Autodesk Fusion 360 part; units mm, degrees
(part 4 of 5)
  spline S15 degree 5 poles (5.856777, 3.833819) (5.854947, 3.833842) (5.851291, 3.833884) (5.845814, 3.833942) (5.838525, 3.834007) (5.829438, 3.834066) (5.820373, 3.834104) (5.811333, 3.834121) (5.802315, 3.834116) (5.793322, 3.83409) (5.784352, 3.834043) (5.775406, 3.833975) (5.766483, 3.833886) (5.757585, 3.833776) (5.748711, 3.833645) (5.739862, 3.833494) (5.731037, 3.833323) (5.722236, 3.833131) (5.71346, 3.832918) (5.704709, 3.832686) (5.695983, 3.832433) (5.687281, 3.83216) (5.678605, 3.831868) (5.669954, 3.831555) (5.661328, 3.831223) (5.652728, 3.830871) (5.644153, 3.8305) (5.635603, 3.830109) (5.62708, 3.829699) (5.618582, 3.82927) (5.610111, 3.828821) (5.601665, 3.828354) (5.593246, 3.827868) (5.584853, 3.827362) (5.576486, 3.826839) (5.568146, 3.826296) (5.559832, 3.825735) (5.551545, 3.825156) (5.543285, 3.824559) (5.535052, 3.823943) (5.526846, 3.82331) (5.518668, 3.822658) (5.510516, 3.821989) (5.502392, 3.821302) (5.494296, 3.820597) (5.486227, 3.819875) (5.478186, 3.819136) (5.470173, 3.818379) (5.462188, 3.817606) (5.454231, 3.816815) (5.446302, 3.816008) (5.438401, 3.815183) (5.430529, 3.814343) (5.422685, 3.813485) (5.41487, 3.812611) (5.407084, 3.811721) (5.399327, 3.810815) (5.391598, 3.809893) (5.383899, 3.808955) (5.376229, 3.808002) (5.368589, 3.807032) (5.360978, 3.806047) (5.353396, 3.805047) (5.345844, 3.804032) (5.338322, 3.803001) (5.33083, 3.801956) (5.323367, 3.800896) (5.315935, 3.799821) (5.308534, 3.798731) (5.301162, 3.797627) (5.293821, 3.796509) (5.286511, 3.795376) (5.279231, 3.79423) (5.271982, 3.79307) (5.264764, 3.791896) (5.257578, 3.790708) (5.250422, 3.789507) (5.243298, 3.788293) (5.236205, 3.787065) (5.229143, 3.785825) (5.222113, 3.784571) (5.215115, 3.783305) (5.208149, 3.782027) (5.201215, 3.780736) (5.194313, 3.779432) (5.187443, 3.778117) (5.180605, 3.77679) (5.1738, 3.77545) (5.167028, 3.7741) (5.160288, 3.772737) (5.153581, 3.771364) (5.146907, 3.769979) (5.140266, 3.768583) (5.133658, 3.767176) (5.127083, 3.765759) (5.120542, 3.764331) (5.114034, 3.762893) (5.10756, 3.761444) (5.10112, 3.759986) (5.094713, 3.758518) (5.08834, 3.75704) (5.082002, 3.755552) (5.075698, 3.754055) (5.069428, 3.752549) (5.063192, 3.751034) (5.056991, 3.74951) (5.050825, 3.747978) (5.044694, 3.746437) (5.038597, 3.744887) (5.032536, 3.74333) (5.026509, 3.741764) (5.020518, 3.740191) (5.014563, 3.738611) (5.008643, 3.737023) (5.002758, 3.735427) (4.99691, 3.733825) (4.991097, 3.732216) (4.98532, 3.730601) (4.97958, 3.728979) (4.973875, 3.72735) (4.968207, 3.725716) (4.962576, 3.724076) (4.956981, 3.72243) (4.951422, 3.720779) (4.945901, 3.719122) (4.940417, 3.717461) (4.934969, 3.715795) (4.929559, 3.714124) (4.924187, 3.712448) (4.918851, 3.710769) (4.913554, 3.709085) (4.908294, 3.707398) (4.903072, 3.705707) (4.897887, 3.704013) (4.892741, 3.702316) (4.887633, 3.700616) (4.882564, 3.698913) (4.877533, 3.697207) (4.87254, 3.6955) (4.867586, 3.69379) (4.862671, 3.692079) (4.857795, 3.690366) (4.852958, 3.688652) (4.84816, 3.686937) (4.843402, 3.685221) (4.838682, 3.683504) (4.834003, 3.681787) (4.829363, 3.68007) (4.824763, 3.678353) (4.820203, 3.676636) (4.815683, 3.67492) (4.811203, 3.673205) (4.806764, 3.671491) (4.802365, 3.669779) (4.798006, 3.668068) (4.793688, 3.666359) (4.789412, 3.664652) (4.785176, 3.662947) (4.780981, 3.661246) (4.776827, 3.659547) (4.772715, 3.657851) (4.768644, 3.656159) (4.764615, 3.654471) (4.760627, 3.652787) (4.756682, 3.651107) (4.752778, 3.649432) (4.748917, 3.647762) (4.745097, 3.646097) (4.741321, 3.644437) (4.737586, 3.642784) (4.733895, 3.641136) (4.730246, 3.639495) (4.72664, 3.63786) (4.723077, 3.636233) (4.719557, 3.634612) (4.716081, 3.633) (4.712648, 3.631395) (4.709258, 3.629799) (4.705913, 3.628211) (4.702611, 3.626632) (4.699353, 3.625062) (4.696139, 3.623502) (4.69297, 3.621952) (4.689845, 3.620411) (4.686764, 3.618882) (4.683728, 3.617363) (4.680737, 3.615856) (4.677791, 3.61436) (4.67489, 3.612876) (4.672034, 3.611405) (4.669224, 3.609946) (4.666459, 3.6085) (4.663739, 3.607067) (4.661066, 3.605649) (4.658438, 3.604244) (4.655856, 3.602854) (4.653321, 3.601479) (4.650832, 3.600119) (4.648389, 3.598775) (4.645993, 3.597447) (4.643644, 3.596136) (4.641342, 3.594841) (4.639087, 3.593564) (4.636879, 3.592304) (4.634718, 3.591063) (4.632605, 3.58984) (4.63054, 3.588636) (4.628522, 3.587452) (4.626553, 3.586287) (4.624631, 3.585143) (4.622758, 3.58402) (4.620933, 3.582917) (4.619157, 3.581837) (4.617429, 3.580778) (4.61575, 3.579743) (4.614121, 3.57873) (4.61254, 3.577741) (4.611009, 3.576776) (4.609527, 3.575835) (4.608095, 3.57492) (4.606713, 3.57403) (4.605381, 3.573166) (4.604099, 3.572329) (4.602867, 3.571519) (4.601685, 3.570737) (4.600555, 3.569983) (4.599475, 3.569257) (4.598446, 3.568561) (4.597468, 3.567895) (4.596541, 3.56726) (4.595666, 3.566655) (4.594843, 3.566083) (4.594071, 3.565542) (4.593351, 3.565034) (4.592683, 3.56456) (4.592068, 3.564119) (4.591505, 3.563713) (4.590995, 3.563343) (4.590538, 3.563009) (4.590134, 3.562712) (4.589784, 3.562453) (4.589546, 3.562275) (4.589391, 3.562159) (4.589299, 3.562089) (4.589256, 3.562056) knots -1 -1 -1 -1 -1 -1 -0.99583333 -0.99166667 -0.9875 -0.98333333 -0.97916667 -0.975 -0.97083333 -0.96666667 -0.9625 -0.95833333 -0.95416667 -0.95 -0.94583333 -0.94166667 -0.9375 -0.93333333 -0.92916667 -0.925 -0.92083333 -0.91666667 -0.9125 -0.90833333 -0.90416667 -0.9 -0.89583333 -0.89166667 -0.8875 -0.88333333 -0.87916667 -0.875 -0.87083333 -0.86666667 -0.8625 -0.85833333 -0.85416667 -0.85 -0.84583333 -0.84166667 -0.8375 -0.83333333 -0.82916667 -0.825 -0.82083333 -0.81666667 -0.8125 -0.80833333 -0.80416667 -0.8 -0.79583333 -0.79166667 -0.7875 -0.78333333 -0.77916667 -0.775 -0.77083333 -0.76666667 -0.7625 -0.75833333 -0.75416667 -0.75 -0.74583333 -0.74166667 -0.7375 -0.73333333 -0.72916667 -0.725 -0.72083333 -0.71666667 -0.7125 -0.70833333 -0.70416667 -0.7 -0.69583333 -0.69166667 -0.6875 -0.68333333 -0.67916667 -0.675 -0.67083333 -0.66666667 -0.6625 -0.65833333 -0.65416667 -0.65 -0.64583333 -0.64166667 -0.6375 -0.63333333 -0.62916667 -0.625 -0.62083333 -0.61666667 -0.6125 -0.60833333 -0.60416667 -0.6 -0.59583333 -0.59166667 -0.5875 -0.58333333 -0.57916667 -0.575 -0.57083333 -0.56666667 -0.5625 -0.55833333 -0.55416667 -0.55 -0.54583333 -0.54166667 -0.5375 -0.53333333 -0.52916667 -0.525 -0.52083333 -0.51666667 -0.5125 -0.50833333 -0.50416667 -0.5 -0.49583333 -0.49166667 -0.4875 -0.48333333 -0.47916667 -0.475 -0.47083333 -0.46666667 -0.4625 -0.45833333 -0.45416667 -0.45 -0.44583333 -0.44166667 -0.4375 -0.43333333 -0.42916667 -0.425 -0.42083333 -0.41666667 -0.4125 -0.40833333 -0.40416667 -0.4 -0.39583333 -0.39166667 -0.3875 -0.38333333 -0.37916667 -0.375 -0.37083333 -0.36666667 -0.3625 -0.35833333 -0.35416667 -0.35 -0.34583333 -0.34166667 -0.3375 -0.33333333 -0.32916667 -0.325 -0.32083333 -0.31666667 -0.3125 -0.30833333 -0.30416667 -0.3 -0.29583333 -0.29166667 -0.2875 -0.28333333 -0.27916667 -0.275 -0.27083333 -0.26666667 -0.2625 -0.25833333 -0.25416667 -0.25 -0.24583333 -0.24166667 -0.2375 -0.23333333 -0.22916667 -0.225 -0.22083333 -0.21666667 -0.2125 -0.20833333 -0.20416667 -0.2 -0.19583333 -0.19166667 -0.1875 -0.18333333 -0.17916667 -0.175 -0.17083333 -0.16666667 -0.1625 -0.15833333 -0.15416667 -0.15 -0.14583333 -0.14166667 -0.1375 -0.13333333 -0.12916667 -0.125 -0.12083333 -0.11666667 -0.1125 -0.10833333 -0.10416667 -0.1 -0.09583333 -0.09166667 -0.0875 -0.08333333 -0.07916667 -0.075 -0.07083333 -0.06666667 -0.0625 -0.05833333 -0.05416667 -0.05 -0.04583333 -0.04166667 -0.0375 -0.03333333 -0.02916667 -0.025 -0.02083333 -0.01666667 -0.0125 -0.00833333 -0.00416667 0 0 0 0 0 0
  line L30 (4.589256, 3.562056) -> (4.58882, 3.561725)
  line L31 (4.58882, 3.561725) -> (3.752337, 2.912468)
  arc A16 (3.752337, 2.912468) -> (2.912468, 3.752337) centre (0, 0) ccw
  line L32 (2.912468, 3.752337) -> (3.561725, 4.58882)
  line L33 (3.561725, 4.58882) -> (3.562056, 4.589256)
  spline S16 degree 5 poles (3.562056, 4.589256) (3.562089, 4.589299) (3.562159, 4.589391) (3.562275, 4.589546) (3.562453, 4.589784) (3.562712, 4.590134) (3.563009, 4.590538) (3.563343, 4.590995) (3.563713, 4.591505) (3.564119, 4.592068) (3.56456, 4.592683) (3.565034, 4.593351) (3.565542, 4.594071) (3.566083, 4.594843) (3.566655, 4.595666) (3.56726, 4.596541) (3.567895, 4.597468) (3.568561, 4.598446) (3.569257, 4.599475) (3.569983, 4.600555) (3.570737, 4.601685) (3.571519, 4.602867) (3.572329, 4.604099) (3.573166, 4.605381) (3.57403, 4.606713) (3.57492, 4.608095) (3.575835, 4.609527) (3.576776, 4.611009) (3.577741, 4.61254) (3.57873, 4.614121) (3.579743, 4.61575) (3.580778, 4.617429) (3.581837, 4.619157) (3.582917, 4.620933) (3.58402, 4.622758) (3.585143, 4.624631) (3.586287, 4.626553) (3.587452, 4.628522) (3.588636, 4.63054) (3.58984, 4.632605) (3.591063, 4.634718) (3.592304, 4.636879) (3.593564, 4.639087) (3.594841, 4.641342) (3.596136, 4.643644) (3.597447, 4.645993) (3.598775, 4.648389) (3.600119, 4.650832) (3.601479, 4.653321) (3.602854, 4.655856) (3.604244, 4.658438) (3.605649, 4.661066) (3.607067, 4.663739) (3.6085, 4.666459) (3.609946, 4.669224) (3.611405, 4.672034) (3.612876, 4.67489) (3.61436, 4.677791) (3.615856, 4.680737) (3.617363, 4.683728) (3.618882, 4.686764) (3.620411, 4.689845) (3.621952, 4.69297) (3.623502, 4.696139) (3.625062, 4.699353) (3.626632, 4.702611) (3.628211, 4.705913) (3.629799, 4.709258) (3.631395, 4.712648) (3.633, 4.716081) (3.634612, 4.719557) (3.636233, 4.723077) (3.63786, 4.72664) (3.639495, 4.730246) (3.641136, 4.733895) (3.642784, 4.737586) (3.644437, 4.741321) (3.646097, 4.745097) (3.647762, 4.748917) (3.649432, 4.752778) (3.651107, 4.756682) (3.652787, 4.760627) (3.654471, 4.764615) (3.656159, 4.768644) (3.657851, 4.772715) (3.659547, 4.776827) (3.661246, 4.780981) (3.662947, 4.785176) (3.664652, 4.789412) (3.666359, 4.793688) (3.668068, 4.798006) (3.669779, 4.802365) (3.671491, 4.806764) (3.673205, 4.811203) (3.67492, 4.815683) (3.676636, 4.820203) (3.678353, 4.824763) (3.68007, 4.829363) (3.681787, 4.834003) (3.683504, 4.838682) (3.685221, 4.843402) (3.686937, 4.84816) (3.688652, 4.852958) (3.690366, 4.857795) (3.692079, 4.862671) (3.69379, 4.867586) (3.6955, 4.87254) (3.697207, 4.877533) (3.698913, 4.882564) (3.700616, 4.887633) (3.702316, 4.892741) (3.704013, 4.897887) (3.705707, 4.903072) (3.707398, 4.908294) (3.709085, 4.913554) (3.710769, 4.918851) (3.712448, 4.924187) (3.714124, 4.929559) (3.715795, 4.934969) (3.717461, 4.940417) (3.719122, 4.945901) (3.720779, 4.951422) (3.72243, 4.956981) (3.724076, 4.962576) (3.725716, 4.968207) (3.72735, 4.973875) (3.728979, 4.97958) (3.730601, 4.98532) (3.732216, 4.991097) (3.733825, 4.99691) (3.735427, 5.002758) (3.737023, 5.008643) (3.738611, 5.014563) (3.740191, 5.020518) (3.741764, 5.026509) (3.74333, 5.032536) (3.744887, 5.038597) (3.746437, 5.044694) (3.747978, 5.050825) (3.74951, 5.056991) (3.751034, 5.063192) (3.752549, 5.069428) (3.754055, 5.075698) (3.755552, 5.082002) (3.75704, 5.08834) (3.758518, 5.094713) (3.759986, 5.10112) (3.761444, 5.10756) (3.762893, 5.114034) (3.764331, 5.120542) (3.765759, 5.127083) (3.767176, 5.133658) (3.768583, 5.140266) (3.769979, 5.146907) (3.771364, 5.153581) (3.772737, 5.160288) (3.7741, 5.167028) (3.77545, 5.1738) (3.77679, 5.180605) (3.778117, 5.187443) (3.779432, 5.194313) (3.780736, 5.201215) (3.782027, 5.208149) (3.783305, 5.215115) (3.784571, 5.222113) (3.785825, 5.229143) (3.787065, 5.236205) (3.788293, 5.243298) (3.789507, 5.250422) (3.790708, 5.257578) (3.791896, 5.264764) (3.79307, 5.271982) (3.79423, 5.279231) (3.795376, 5.286511) (3.796509, 5.293821) (3.797627, 5.301162) (3.798731, 5.308534) (3.799821, 5.315935) (3.800896, 5.323367) (3.801956, 5.33083) (3.803001, 5.338322) (3.804032, 5.345844) (3.805047, 5.353396) (3.806047, 5.360978) (3.807032, 5.368589) (3.808002, 5.376229) (3.808955, 5.383899) (3.809893, 5.391598) (3.810815, 5.399327) (3.811721, 5.407084) (3.812611, 5.41487) (3.813485, 5.422685) (3.814343, 5.430529) (3.815183, 5.438401) (3.816008, 5.446302) (3.816815, 5.454231) (3.817606, 5.462188) (3.818379, 5.470173) (3.819136, 5.478186) (3.819875, 5.486227) (3.820597, 5.494296) (3.821302, 5.502392) (3.821989, 5.510516) (3.822658, 5.518668) (3.82331, 5.526846) (3.823943, 5.535052) (3.824559, 5.543285) (3.825156, 5.551545) (3.825735, 5.559832) (3.826296, 5.568146) (3.826839, 5.576486) (3.827362, 5.584853) (3.827868, 5.593246) (3.828354, 5.601665) (3.828821, 5.610111) (3.82927, 5.618582) (3.829699, 5.62708) (3.830109, 5.635603) (3.8305, 5.644153) (3.830871, 5.652728) (3.831223, 5.661328) (3.831555, 5.669954) (3.831868, 5.678605) (3.83216, 5.687281) (3.832433, 5.695983) (3.832686, 5.704709) (3.832918, 5.71346) (3.833131, 5.722236) (3.833323, 5.731037) (3.833494, 5.739862) (3.833645, 5.748711) (3.833776, 5.757585) (3.833886, 5.766483) (3.833975, 5.775406) (3.834043, 5.784352) (3.83409, 5.793322) (3.834116, 5.802315) (3.834121, 5.811333) (3.834104, 5.820373) (3.834066, 5.829438) (3.834007, 5.838525) (3.833942, 5.845814) (3.833884, 5.851291) (3.833842, 5.854947) (3.833819, 5.856777) knots 0 0 0 0 0 0 0.00416667 0.00833333 0.0125 0.01666667 0.02083333 0.025 0.02916667 0.03333333 0.0375 0.04166667 0.04583333 0.05 0.05416667 0.05833333 0.0625 0.06666667 0.07083333 0.075 0.07916667 0.08333333 0.0875 0.09166667 0.09583333 0.1 0.10416667 0.10833333 0.1125 0.11666667 0.12083333 0.125 0.12916667 0.13333333 0.1375 0.14166667 0.14583333 0.15 0.15416667 0.15833333 0.1625 0.16666667 0.17083333 0.175 0.17916667 0.18333333 0.1875 0.19166667 0.19583333 0.2 0.20416667 0.20833333 0.2125 0.21666667 0.22083333 0.225 0.22916667 0.23333333 0.2375 0.24166667 0.24583333 0.25 0.25416667 0.25833333 0.2625 0.26666667 0.27083333 0.275 0.27916667 0.28333333 0.2875 0.29166667 0.29583333 0.3 0.30416667 0.30833333 0.3125 0.31666667 0.32083333 0.325 0.32916667 0.33333333 0.3375 0.34166667 0.34583333 0.35 0.35416667 0.35833333 0.3625 0.36666667 0.37083333 0.375 0.37916667 0.38333333 0.3875 0.39166667 0.39583333 0.4 0.40416667 0.40833333 0.4125 0.41666667 0.42083333 0.425 0.42916667 0.43333333 0.4375 0.44166667 0.44583333 0.45 0.45416667 0.45833333 0.4625 0.46666667 0.47083333 0.475 0.47916667 0.48333333 0.4875 0.49166667 0.49583333 0.5 0.50416667 0.50833333 0.5125 0.51666667 0.52083333 0.525 0.52916667 0.53333333 0.5375 0.54166667 0.54583333 0.55 0.55416667 0.55833333 0.5625 0.56666667 0.57083333 0.575 0.57916667 0.58333333 0.5875 0.59166667 0.59583333 0.6 0.60416667 0.60833333 0.6125 0.61666667 0.62083333 0.625 0.62916667 0.63333333 0.6375 0.64166667 0.64583333 0.65 0.65416667 0.65833333 0.6625 0.66666667 0.67083333 0.675 0.67916667 0.68333333 0.6875 0.69166667 0.69583333 0.7 0.70416667 0.70833333 0.7125 0.71666667 0.72083333 0.725 0.72916667 0.73333333 0.7375 0.74166667 0.74583333 0.75 0.75416667 0.75833333 0.7625 0.76666667 0.77083333 0.775 0.77916667 0.78333333 0.7875 0.79166667 0.79583333 0.8 0.80416667 0.80833333 0.8125 0.81666667 0.82083333 0.825 0.82916667 0.83333333 0.8375 0.84166667 0.84583333 0.85 0.85416667 0.85833333 0.8625 0.86666667 0.87083333 0.875 0.87916667 0.88333333 0.8875 0.89166667 0.89583333 0.9 0.90416667 0.90833333 0.9125 0.91666667 0.92083333 0.925 0.92916667 0.93333333 0.9375 0.94166667 0.94583333 0.95 0.95416667 0.95833333 0.9625 0.96666667 0.97083333 0.975 0.97916667 0.98333333 0.9875 0.99166667 0.99583333 1 1 1 1 1 1
  arc A17 (3.833819, 5.856777) -> (3.155208, 6.248573) centre (0, 0) ccw
  spline S17 degree 5 poles (3.155208, 6.248573) (3.153612, 6.247678) (3.150425, 6.245887) (3.145652, 6.243199) (3.139308, 6.23961) (3.131408, 6.235117) (3.123539, 6.230618) (3.115701, 6.226112) (3.107895, 6.2216) (3.100119, 6.21708) (3.092374, 6.212555) (3.084661, 6.208022) (3.076978, 6.203484) (3.069327, 6.19894) (3.061707, 6.19439) (3.054119, 6.189834) (3.046562, 6.185273) (3.039036, 6.180707) (3.031542, 6.176135) (3.02408, 6.171558) (3.016649, 6.166976) (3.00925, 6.162389) (3.001882, 6.157797) (2.994546, 6.153201) (2.987242, 6.148601) (2.97997, 6.143996) (2.97273, 6.139387) (2.965521, 6.134774) (2.958345, 6.130157) (2.9512, 6.125536) (2.944088, 6.120912) (2.937007, 6.116284) (2.929959, 6.111653) (2.922943, 6.107019) (2.915959, 6.102382) (2.909007, 6.097743) (2.902088, 6.0931) (2.895201, 6.088455) (2.888347, 6.083808) (2.881524, 6.079158) (2.874735, 6.074507) (2.867977, 6.069853) (2.861253, 6.065198) (2.854561, 6.060541) (2.847901, 6.055882) (2.841274, 6.051223) (2.83468, 6.046562) (2.828119, 6.0419) (2.82159, 6.037237) (2.815095, 6.032574) (2.808632, 6.02791) (2.802202, 6.023246) (2.795805, 6.018582) (2.789441, 6.013918) (2.78311, 6.009253) (2.776811, 6.00459) (2.770546, 5.999926) (2.764315, 5.995264) (2.758116, 5.990602) (2.75195, 5.985941) (2.745818, 5.981281) (2.739719, 5.976622) (2.733653, 5.971966) (2.727621, 5.96731) (2.721622, 5.962657) (2.715656, 5.958005) (2.709724, 5.953356) (2.703825, 5.948709) (2.697959, 5.944064) (2.692128, 5.939423) (2.686329, 5.934784) (2.680564, 5.930148) (2.674833, 5.925515) (2.669136, 5.920886) (2.663472, 5.91626) (2.657842, 5.911638) (2.652245, 5.90702) (2.646683, 5.902407) (2.641154, 5.897797) (2.635658, 5.893192) (2.630197, 5.888592) (2.62477, 5.883996) (2.619376, 5.879406) (2.614016, 5.874821) (2.608691, 5.870241) (2.603399, 5.865667) (2.598141, 5.861098) (2.592917, 5.856536) (2.587728, 5.85198) (2.582572, 5.84743) (2.57745, 5.842887) (2.572363, 5.838351) (2.567309, 5.833822) (2.56229, 5.829299) (2.557305, 5.824785) (2.552354, 5.820277) (2.547437, 5.815778) (2.542554, 5.811286) (2.537706, 5.806803) (2.532892, 5.802328) (2.528112, 5.797862) (2.523367, 5.793404) (2.518656, 5.788956) (2.513979, 5.784517) (2.509336, 5.780087) (2.504728, 5.775667) (2.500154, 5.771256) (2.495615, 5.766856) (2.49111, 5.762466) (2.486639, 5.758087) (2.482203, 5.753718) (2.477801, 5.74936) (2.473433, 5.745013) (2.469101, 5.740678) (2.464802, 5.736354) (2.460538, 5.732042) (2.456309, 5.727743) (2.452114, 5.723455) (2.447953, 5.71918) (2.443827, 5.714918) (2.439736, 5.710668) (2.435679, 5.706432) (2.431656, 5.702209) (2.427668, 5.698) (2.423715, 5.693805) (2.419796, 5.689624) (2.415912, 5.685457) (2.412062, 5.681305) (2.408247, 5.677168) (2.404466, 5.673046) (2.40072, 5.668939) (2.397008, 5.664848) (2.393331, 5.660772) (2.389688, 5.656713) (2.38608, 5.65267) (2.382507, 5.648644) (2.378968, 5.644634) (2.375463, 5.640642) (2.371994, 5.636667) (2.368558, 5.632709) (2.365157, 5.62877) (2.361791, 5.624848) (2.358459, 5.620945) (2.355161, 5.617061) (2.351898, 5.613196) (2.34867, 5.609349) (2.345476, 5.605523) (2.342316, 5.601716) (2.339191, 5.597929) (2.3361, 5.594162) (2.333044, 5.590416) (2.330022, 5.586691) (2.327034, 5.582987) (2.32408, 5.579304) (2.321161, 5.575643) (2.318277, 5.572004) (2.315426, 5.568387) (2.31261, 5.564793) (2.309828, 5.561222) (2.30708, 5.557674) (2.304367, 5.55415) (2.301687, 5.550649) (2.299042, 5.547172) (2.296431, 5.54372) (2.293854, 5.540293) (2.29131, 5.53689) (2.288801, 5.533513) (2.286326, 5.530161) (2.283885, 5.526836) (2.281478, 5.523536) (2.279105, 5.520264) (2.276766, 5.517018) (2.27446, 5.513799) (2.272188, 5.510608) (2.26995, 5.507445) (2.267746, 5.50431) (2.265575, 5.501204) (2.263438, 5.498127) (2.261334, 5.495079) (2.259264, 5.492061) (2.257228, 5.489072) (2.255225, 5.486114) (2.253255, 5.483187) (2.251319, 5.480291) (2.249416, 5.477426) (2.247546, 5.474593) (2.245709, 5.471792) (2.243906, 5.469023) (2.242135, 5.466288) (2.240398, 5.463585) (2.238693, 5.460917) (2.237022, 5.458282) (2.235383, 5.455682) (2.233777, 5.453116) (2.232203, 5.450586) (2.230663, 5.448092) (2.229155, 5.445633) (2.227679, 5.443211) (2.226236, 5.440826) (2.224825, 5.438478) (2.223446, 5.436167) (2.2221, 5.433895) (2.220785, 5.431661) (2.219503, 5.429466) (2.218252, 5.427311) (2.217034, 5.425195) (2.215847, 5.42312) (2.214692, 5.421086) (2.213569, 5.419092) (2.212477, 5.417141) (2.211416, 5.415231) (2.210387, 5.413364) (2.209389, 5.41154) (2.208422, 5.40976) (2.207486, 5.408023) (2.206581, 5.406331) (2.205707, 5.404684) (2.204863, 5.403083) (2.20405, 5.401528) (2.203268, 5.400019) (2.202515, 5.398557) (2.201794, 5.397143) (2.201102, 5.395777) (2.20044, 5.39446) (2.199808, 5.393192) (2.199206, 5.391973) (2.198633, 5.390805) (2.19809, 5.389688) (2.197576, 5.388622) (2.197091, 5.387608) (2.196636, 5.386647) (2.196209, 5.385739) (2.195811, 5.384885) (2.195442, 5.384086) (2.195101, 5.383341) (2.194788, 5.382652) (2.194504, 5.382019) (2.194247, 5.381443) (2.194018, 5.380926) (2.193817, 5.380467) (2.193643, 5.380067) (2.193526, 5.379794) (2.19345, 5.379616) (2.193405, 5.379509) (2.193384, 5.379459) knots -1 -1 -1 -1 -1 -1 -0.99583333 -0.99166667 -0.9875 -0.98333333 -0.97916667 -0.975 -0.97083333 -0.96666667 -0.9625 -0.95833333 -0.95416667 -0.95 -0.94583333 -0.94166667 -0.9375 -0.93333333 -0.92916667 -0.925 -0.92083333 -0.91666667 -0.9125 -0.90833333 -0.90416667 -0.9 -0.89583333 -0.89166667 -0.8875 -0.88333333 -0.87916667 -0.875 -0.87083333 -0.86666667 -0.8625 -0.85833333 -0.85416667 -0.85 -0.84583333 -0.84166667 -0.8375 -0.83333333 -0.82916667 -0.825 -0.82083333 -0.81666667 -0.8125 -0.80833333 -0.80416667 -0.8 -0.79583333 -0.79166667 -0.7875 -0.78333333 -0.77916667 -0.775 -0.77083333 -0.76666667 -0.7625 -0.75833333 -0.75416667 -0.75 -0.74583333 -0.74166667 -0.7375 -0.73333333 -0.72916667 -0.725 -0.72083333 -0.71666667 -0.7125 -0.70833333 -0.70416667 -0.7 -0.69583333 -0.69166667 -0.6875 -0.68333333 -0.67916667 -0.675 -0.67083333 -0.66666667 -0.6625 -0.65833333 -0.65416667 -0.65 -0.64583333 -0.64166667 -0.6375 -0.63333333 -0.62916667 -0.625 -0.62083333 -0.61666667 -0.6125 -0.60833333 -0.60416667 -0.6 -0.59583333 -0.59166667 -0.5875 -0.58333333 -0.57916667 -0.575 -0.57083333 -0.56666667 -0.5625 -0.55833333 -0.55416667 -0.55 -0.54583333 -0.54166667 -0.5375 -0.53333333 -0.52916667 -0.525 -0.52083333 -0.51666667 -0.5125 -0.50833333 -0.50416667 -0.5 -0.49583333 -0.49166667 -0.4875 -0.48333333 -0.47916667 -0.475 -0.47083333 -0.46666667 -0.4625 -0.45833333 -0.45416667 -0.45 -0.44583333 -0.44166667 -0.4375 -0.43333333 -0.42916667 -0.425 -0.42083333 -0.41666667 -0.4125 -0.40833333 -0.40416667 -0.4 -0.39583333 -0.39166667 -0.3875 -0.38333333 -0.37916667 -0.375 -0.37083333 -0.36666667 -0.3625 -0.35833333 -0.35416667 -0.35 -0.34583333 -0.34166667 -0.3375 -0.33333333 -0.32916667 -0.325 -0.32083333 -0.31666667 -0.3125 -0.30833333 -0.30416667 -0.3 -0.29583333 -0.29166667 -0.2875 -0.28333333 -0.27916667 -0.275 -0.27083333 -0.26666667 -0.2625 -0.25833333 -0.25416667 -0.25 -0.24583333 -0.24166667 -0.2375 -0.23333333 -0.22916667 -0.225 -0.22083333 -0.21666667 -0.2125 -0.20833333 -0.20416667 -0.2 -0.19583333 -0.19166667 -0.1875 -0.18333333 -0.17916667 -0.175 -0.17083333 -0.16666667 -0.1625 -0.15833333 -0.15416667 -0.15 -0.14583333 -0.14166667 -0.1375 -0.13333333 -0.12916667 -0.125 -0.12083333 -0.11666667 -0.1125 -0.10833333 -0.10416667 -0.1 -0.09583333 -0.09166667 -0.0875 -0.08333333 -0.07916667 -0.075 -0.07083333 -0.06666667 -0.0625 -0.05833333 -0.05416667 -0.05 -0.04583333 -0.04166667 -0.0375 -0.03333333 -0.02916667 -0.025 -0.02083333 -0.01666667 -0.0125 -0.00833333 -0.00416667 0 0 0 0 0 0
  line L34 (2.193384, 5.379459) -> (2.193173, 5.378954)
  line L35 (2.193173, 5.378954) -> (1.793385, 4.398439)
  arc A18 (1.793385, 4.398439) -> (0.646102, 4.705853) centre (0, 0) ccw
  line L36 (0.646102, 4.705853) -> (0.790134, 5.754897)
  line L37 (0.790134, 5.754897) -> (0.790203, 5.75544)
  spline S18 degree 5 poles (0.790203, 5.75544) (0.79021, 5.755494) (0.790225, 5.755609) (0.790248, 5.755801) (0.790283, 5.756096) (0.790332, 5.756529) (0.790387, 5.757027) (0.790448, 5.75759) (0.790513, 5.758217) (0.790584, 5.758907) (0.790657, 5.75966) (0.790735, 5.760476) (0.790815, 5.761353) (0.790897, 5.762292) (0.790981, 5.763291) (0.791067, 5.764351) (0.791154, 5.765472) (0.791242, 5.766651) (0.79133, 5.767891) (0.791419, 5.769189) (0.791506, 5.770545) (0.791593, 5.771959) (0.791679, 5.773431) (0.791762, 5.77496) (0.791844, 5.776545) (0.791924, 5.778187) (0.792001, 5.779885) (0.792074, 5.781639) (0.792144, 5.783447) (0.792211, 5.785311) (0.792273, 5.787228) (0.79233, 5.7892) (0.792383, 5.791225) (0.792431, 5.793304) (0.792473, 5.795436) (0.792509, 5.79762) (0.79254, 5.799856) (0.792563, 5.802144) (0.79258, 5.804483) (0.79259, 5.806874) (0.792593, 5.809315) (0.792587, 5.811807) (0.792574, 5.814349) (0.792553, 5.816941) (0.792523, 5.819582) (0.792484, 5.822272) (0.792436, 5.825011) (0.792379, 5.827798) (0.792312, 5.830634) (0.792235, 5.833517) (0.792148, 5.836448) (0.792051, 5.839426) (0.791942, 5.84245) (0.791823, 5.845522) (0.791693, 5.848639) (0.791551, 5.851802) (0.791398, 5.855011) (0.791232, 5.858266) (0.791054, 5.861565) (0.790864, 5.864909) (0.790662, 5.868298) (0.790446, 5.87173) (0.790217, 5.875207) (0.789975, 5.878727) (0.789719, 5.88229) (0.78945, 5.885896) (0.789166, 5.889545) (0.788869, 5.893237) (0.788557, 5.89697) (0.78823, 5.900746) (0.787888, 5.904563) (0.787532, 5.908421) (0.78716, 5.91232) (0.786772, 5.91626) (0.786369, 5.920241) (0.78595, 5.924262) (0.785515, 5.928323) (0.785064, 5.932423) (0.784596, 5.936563) (0.784112, 5.940743) (0.783611, 5.944961) (0.783093, 5.949218) (0.782558, 5.953513) (0.782005, 5.957847) (0.781435, 5.962218) (0.780847, 5.966627) (0.780241, 5.971074) (0.779618, 5.975557) (0.778976, 5.980078) (0.778316, 5.984635) (0.777637, 5.989229) (0.776939, 5.993859) (0.776223, 5.998525) (0.775487, 6.003227) (0.774733, 6.007964) (0.773959, 6.012736) (0.773166, 6.017544) (0.772353, 6.022386) (0.77152, 6.027263) (0.770667, 6.032174) (0.769794, 6.037119) (0.768901, 6.042098) (0.767987, 6.047111) (0.767053, 6.052157) (0.766099, 6.057236) (0.765123, 6.062348) (0.764127, 6.067493) (0.763109, 6.072671) (0.762071, 6.077881) (0.76101, 6.083122) (0.759929, 6.088396) (0.758826, 6.093701) (0.757701, 6.099038) (0.756554, 6.104406) (0.755385, 6.109805) (0.754194, 6.115235) (0.752981, 6.120695) (0.751746, 6.126185) (0.750488, 6.131706) (0.749207, 6.137257) (0.747904, 6.142837) (0.746578, 6.148447) (0.745229, 6.154086) (0.743856, 6.159754) (0.742461, 6.165452) (0.741042, 6.171177) (0.7396, 6.176932) (0.738135, 6.182714) (0.736646, 6.188525) (0.735133, 6.194363) (0.733596, 6.20023) (0.732035, 6.206123) (0.73045, 6.212044) (0.728842, 6.217992) (0.727208, 6.223967) (0.725551, 6.229969) (0.723869, 6.235997) (0.722162, 6.242051) (0.720431, 6.248132) (0.718675, 6.254238) (0.716895, 6.26037) (0.715089, 6.266528) (0.713258, 6.272711) (0.711403, 6.278919) (0.709522, 6.285152) (0.707615, 6.29141) (0.705684, 6.297692) (0.703726, 6.303999) (0.701744, 6.31033) (0.699735, 6.316685) (0.697701, 6.323064) (0.695642, 6.329466) (0.693556, 6.335892) (0.691444, 6.342342) (0.689306, 6.348814) (0.687142, 6.355309) (0.684952, 6.361827) (0.682736, 6.368368) (0.680493, 6.374931) (0.678224, 6.381516) (0.675928, 6.388123) (0.673606, 6.394752) (0.671257, 6.401403) (0.668881, 6.408075) (0.666478, 6.414769) (0.664049, 6.421483) (0.661592, 6.428219) (0.659109, 6.434975) (0.656598, 6.441752) (0.654061, 6.44855) (0.651496, 6.455368) (0.648904, 6.462205) (0.646284, 6.469063) (0.643637, 6.475941) (0.640963, 6.482838) (0.63826, 6.489755) (0.635531, 6.49669) (0.632773, 6.503645) (0.629988, 6.510619) (0.627176, 6.517612) (0.624335, 6.524623) (0.621466, 6.531653) (0.61857, 6.5387) (0.615645, 6.545766) (0.612692, 6.55285) (0.609711, 6.559952) (0.606702, 6.567071) (0.603665, 6.574208) (0.6006, 6.581362) (0.597506, 6.588533) (0.594383, 6.595721) (0.591232, 6.602926) (0.588053, 6.610147) (0.584845, 6.617385) (0.581609, 6.624639) (0.578344, 6.63191) (0.57505, 6.639196) (0.571727, 6.646498) (0.568376, 6.653816) (0.564995, 6.66115) (0.561586, 6.668499) (0.558148, 6.675863) (0.554681, 6.683242) (0.551185, 6.690636) (0.54766, 6.698044) (0.544106, 6.705468) (0.540522, 6.712905) (0.53691, 6.720357) (0.533268, 6.727824) (0.529597, 6.735304) (0.525897, 6.742798) (0.522167, 6.750305) (0.518408, 6.757827) (0.514619, 6.765361) (0.510801, 6.772909) (0.506954, 6.78047) (0.503077, 6.788044) (0.49917, 6.79563) (0.495234, 6.80323) (0.491268, 6.810841) (0.487273, 6.818465) (0.483247, 6.826102) (0.479192, 6.83375) (0.475108, 6.84141) (0.470993, 6.849082) (0.466849, 6.856766) (0.462675, 6.864461) (0.458471, 6.872167) (0.454236, 6.879885) (0.449973, 6.887613) (0.445679, 6.895353) (0.441355, 6.903103) (0.437001, 6.910864) (0.432617, 6.918635) (0.428203, 6.926417) (0.423758, 6.934209) (0.419284, 6.942011) (0.41478, 6.949822) (0.410245, 6.957643) (0.40568, 6.965474) (0.401085, 6.973315) (0.397385, 6.979595) (0.394596, 6.984309) (0.39273, 6.987454) (0.391796, 6.989027) knots 0 0 0 0 0 0 0.00416667 0.00833333 0.0125 0.01666667 0.02083333 0.025 0.02916667 0.03333333 0.0375 0.04166667 0.04583333 0.05 0.05416667 0.05833333 0.0625 0.06666667 0.07083333 0.075 0.07916667 0.08333333 0.0875 0.09166667 0.09583333 0.1 0.10416667 0.10833333 0.1125 0.11666667 0.12083333 0.125 0.12916667 0.13333333 0.1375 0.14166667 0.14583333 0.15 0.15416667 0.15833333 0.1625 0.16666667 0.17083333 0.175 0.17916667 0.18333333 0.1875 0.19166667 0.19583333 0.2 0.20416667 0.20833333 0.2125 0.21666667 0.22083333 0.225 0.22916667 0.23333333 0.2375 0.24166667 0.24583333 0.25 0.25416667 0.25833333 0.2625 0.26666667 0.27083333 0.275 0.27916667 0.28333333 0.2875 0.29166667 0.29583333 0.3 0.30416667 0.30833333 0.3125 0.31666667 0.32083333 0.325 0.32916667 0.33333333 0.3375 0.34166667 0.34583333 0.35 0.35416667 0.35833333 0.3625 0.36666667 0.37083333 0.375 0.37916667 0.38333333 0.3875 0.39166667 0.39583333 0.4 0.40416667 0.40833333 0.4125 0.41666667 0.42083333 0.425 0.42916667 0.43333333 0.4375 0.44166667 0.44583333 0.45 0.45416667 0.45833333 0.4625 0.46666667 0.47083333 0.475 0.47916667 0.48333333 0.4875 0.49166667 0.49583333 0.5 0.50416667 0.50833333 0.5125 0.51666667 0.52083333 0.525 0.52916667 0.53333333 0.5375 0.54166667 0.54583333 0.55 0.55416667 0.55833333 0.5625 0.56666667 0.57083333 0.575 0.57916667 0.58333333 0.5875 0.59166667 0.59583333 0.6 0.60416667 0.60833333 0.6125 0.61666667 0.62083333 0.625 0.62916667 0.63333333 0.6375 0.64166667 0.64583333 0.65 0.65416667 0.65833333 0.6625 0.66666667 0.67083333 0.675 0.67916667 0.68333333 0.6875 0.69166667 0.69583333 0.7 0.70416667 0.70833333 0.7125 0.71666667 0.72083333 0.725 0.72916667 0.73333333 0.7375 0.74166667 0.74583333 0.75 0.75416667 0.75833333 0.7625 0.76666667 0.77083333 0.775 0.77916667 0.78333333 0.7875 0.79166667 0.79583333 0.8 0.80416667 0.80833333 0.8125 0.81666667 0.82083333 0.825 0.82916667 0.83333333 0.8375 0.84166667 0.84583333 0.85 0.85416667 0.85833333 0.8625 0.86666667 0.87083333 0.875 0.87916667 0.88333333 0.8875 0.89166667 0.89583333 0.9 0.90416667 0.90833333 0.9125 0.91666667 0.92083333 0.925 0.92916667 0.93333333 0.9375 0.94166667 0.94583333 0.95 0.95416667 0.95833333 0.9625 0.96666667 0.97083333 0.975 0.97916667 0.98333333 0.9875 0.99166667 0.99583333 1 1 1 1 1 1
  arc A19 (0.391796, 6.989027) -> (-0.391796, 6.989027) centre (0, 0) ccw
  spline S19 degree 5 poles (-0.391796, 6.989027) (-0.39273, 6.987454) (-0.394596, 6.984309) (-0.397385, 6.979595) (-0.401085, 6.973315) (-0.40568, 6.965474) (-0.410245, 6.957643) (-0.41478, 6.949822) (-0.419284, 6.942011) (-0.423758, 6.934209) (-0.428203, 6.926417) (-0.432617, 6.918635) (-0.437001, 6.910864) (-0.441355, 6.903103) (-0.445679, 6.895353) (-0.449973, 6.887613) (-0.454236, 6.879885) (-0.458471, 6.872167) (-0.462675, 6.864461) (-0.466849, 6.856766) (-0.470993, 6.849082) (-0.475108, 6.84141) (-0.479192, 6.83375) (-0.483247, 6.826102) (-0.487273, 6.818465) (-0.491268, 6.810841) (-0.495234, 6.80323) (-0.49917, 6.79563) (-0.503077, 6.788044) (-0.506954, 6.78047) (-0.510801, 6.772909) (-0.514619, 6.765361) (-0.518408, 6.757827) (-0.522167, 6.750305) (-0.525897, 6.742798) (-0.529597, 6.735304) (-0.533268, 6.727824) (-0.53691, 6.720357) (-0.540522, 6.712905) (-0.544106, 6.705468) (-0.54766, 6.698044) (-0.551185, 6.690636) (-0.554681, 6.683242) (-0.558148, 6.675863) (-0.561586, 6.668499) (-0.564995, 6.66115) (-0.568376, 6.653816) (-0.571727, 6.646498) (-0.57505, 6.639196) (-0.578344, 6.63191) (-0.581609, 6.624639) (-0.584845, 6.617385) (-0.588053, 6.610147) (-0.591232, 6.602926) (-0.594383, 6.595721) (-0.597506, 6.588533) (-0.6006, 6.581362) (-0.603665, 6.574208) (-0.606702, 6.567071) (-0.609711, 6.559952) (-0.612692, 6.55285) (-0.615645, 6.545766) (-0.61857, 6.5387) (-0.621466, 6.531653) (-0.624335, 6.524623) (-0.627176, 6.517612) (-0.629988, 6.510619) (-0.632773, 6.503645) (-0.635531, 6.49669) (-0.63826, 6.489755) (-0.640963, 6.482838) (-0.643637, 6.475941) (-0.646284, 6.469063) (-0.648904, 6.462205) (-0.651496, 6.455368) (-0.654061, 6.44855) (-0.656598, 6.441752) (-0.659109, 6.434975) (-0.661592, 6.428219) (-0.664049, 6.421483) (-0.666478, 6.414769) (-0.668881, 6.408075) (-0.671257, 6.401403) (-0.673606, 6.394752) (-0.675928, 6.388123) (-0.678224, 6.381516) (-0.680493, 6.374931) (-0.682736, 6.368368) (-0.684952, 6.361827) (-0.687142, 6.355309) (-0.689306, 6.348814) (-0.691444, 6.342342) (-0.693556, 6.335892) (-0.695642, 6.329466) (-0.697701, 6.323064) (-0.699735, 6.316685) (-0.701744, 6.31033) (-0.703726, 6.303999) (-0.705684, 6.297692) (-0.707615, 6.29141) (-0.709522, 6.285152) (-0.711403, 6.278919) (-0.713258, 6.272711) (-0.715089, 6.266528) (-0.716895, 6.26037) (-0.718675, 6.254238) (-0.720431, 6.248132) (-0.722162, 6.242051) (-0.723869, 6.235997) (-0.725551, 6.229969) (-0.727208, 6.223967) (-0.728842, 6.217992) (-0.73045, 6.212044) (-0.732035, 6.206123) (-0.733596, 6.20023) (-0.735133, 6.194363) (-0.736646, 6.188525) (-0.738135, 6.182714) (-0.7396, 6.176932) (-0.741042, 6.171177) (-0.742461, 6.165452) (-0.743856, 6.159754) (-0.745229, 6.154086) (-0.746578, 6.148447) (-0.747904, 6.142837) (-0.749207, 6.137257) (-0.750488, 6.131706) (-0.751746, 6.126185) (-0.752981, 6.120695) (-0.754194, 6.115235) (-0.755385, 6.109805) (-0.756554, 6.104406) (-0.757701, 6.099038) (-0.758826, 6.093701) (-0.759929, 6.088396) (-0.76101, 6.083122) (-0.762071, 6.077881) (-0.763109, 6.072671) (-0.764127, 6.067493) (-0.765123, 6.062348) (-0.766099, 6.057236) (-0.767053, 6.052157) (-0.767987, 6.047111) (-0.768901, 6.042098) (-0.769794, 6.037119) (-0.770667, 6.032174) (-0.77152, 6.027263) (-0.772353, 6.022386) (-0.773166, 6.017544) (-0.773959, 6.012736) (-0.774733, 6.007964) (-0.775487, 6.003227) (-0.776223, 5.998525) (-0.776939, 5.993859) (-0.777637, 5.989229) (-0.778316, 5.984635) (-0.778976, 5.980078) (-0.779618, 5.975557) (-0.780241, 5.971074) (-0.780847, 5.966627) (-0.781435, 5.962218) (-0.782005, 5.957847) (-0.782558, 5.953513) (-0.783093, 5.949218) (-0.783611, 5.944961) (-0.784112, 5.940743) (-0.784596, 5.936563) (-0.785064, 5.932423) (-0.785515, 5.928323) (-0.78595, 5.924262) (-0.786369, 5.920241) (-0.786772, 5.91626) (-0.78716, 5.91232) (-0.787532, 5.908421) (-0.787888, 5.904563) (-0.78823, 5.900746) (-0.788557, 5.89697) (-0.788869, 5.893237) (-0.789166, 5.889545) (-0.78945, 5.885896) (-0.789719, 5.88229) (-0.789975, 5.878727) (-0.790217, 5.875207) (-0.790446, 5.87173) (-0.790662, 5.868298) (-0.790864, 5.864909) (-0.791054, 5.861565) (-0.791232, 5.858266) (-0.791398, 5.855011) (-0.791551, 5.851802) (-0.791693, 5.848639) (-0.791823, 5.845522) (-0.791942, 5.84245) (-0.792051, 5.839426) (-0.792148, 5.836448) (-0.792235, 5.833517) (-0.792312, 5.830634) (-0.792379, 5.827798) (-0.792436, 5.825011) (-0.792484, 5.822272) (-0.792523, 5.819582) (-0.792553, 5.816941) (-0.792574, 5.814349) (-0.792587, 5.811807) (-0.792593, 5.809315) (-0.79259, 5.806874) (-0.79258, 5.804483) (-0.792563, 5.802144) (-0.79254, 5.799856) (-0.792509, 5.79762) (-0.792473, 5.795436) (-0.792431, 5.793304) (-0.792383, 5.791225) (-0.79233, 5.7892) (-0.792273, 5.787228) (-0.792211, 5.785311) (-0.792144, 5.783447) (-0.792074, 5.781639) (-0.792001, 5.779885) (-0.791924, 5.778187) (-0.791844, 5.776545) (-0.791762, 5.77496) (-0.791679, 5.773431) (-0.791593, 5.771959) (-0.791506, 5.770545) (-0.791419, 5.769189) (-0.79133, 5.767891) (-0.791242, 5.766651) (-0.791154, 5.765472) (-0.791067, 5.764351) (-0.790981, 5.763291) (-0.790897, 5.762292) (-0.790815, 5.761353) (-0.790735, 5.760476) (-0.790657, 5.75966) (-0.790584, 5.758907) (-0.790513, 5.758217) (-0.790448, 5.75759) (-0.790387, 5.757027) (-0.790332, 5.756529) (-0.790283, 5.756096) (-0.790248, 5.755801) (-0.790225, 5.755609) (-0.79021, 5.755494) (-0.790203, 5.75544) knots -1 -1 -1 -1 -1 -1 -0.99583333 -0.99166667 -0.9875 -0.98333333 -0.97916667 -0.975 -0.97083333 -0.96666667 -0.9625 -0.95833333 -0.95416667 -0.95 -0.94583333 -0.94166667 -0.9375 -0.93333333 -0.92916667 -0.925 -0.92083333 -0.91666667 -0.9125 -0.90833333 -0.90416667 -0.9 -0.89583333 -0.89166667 -0.8875 -0.88333333 -0.87916667 -0.875 -0.87083333 -0.86666667 -0.8625 -0.85833333 -0.85416667 -0.85 -0.84583333 -0.84166667 -0.8375 -0.83333333 -0.82916667 -0.825 -0.82083333 -0.81666667 -0.8125 -0.80833333 -0.80416667 -0.8 -0.79583333 -0.79166667 -0.7875 -0.78333333 -0.77916667 -0.775 -0.77083333 -0.76666667 -0.7625 -0.75833333 -0.75416667 -0.75 -0.74583333 -0.74166667 -0.7375 -0.73333333 -0.72916667 -0.725 -0.72083333 -0.71666667 -0.7125 -0.70833333 -0.70416667 -0.7 -0.69583333 -0.69166667 -0.6875 -0.68333333 -0.67916667 -0.675 -0.67083333 -0.66666667 -0.6625 -0.65833333 -0.65416667 -0.65 -0.64583333 -0.64166667 -0.6375 -0.63333333 -0.62916667 -0.625 -0.62083333 -0.61666667 -0.6125 -0.60833333 -0.60416667 -0.6 -0.59583333 -0.59166667 -0.5875 -0.58333333 -0.57916667 -0.575 -0.57083333 -0.56666667 -0.5625 -0.55833333 -0.55416667 -0.55 -0.54583333 -0.54166667 -0.5375 -0.53333333 -0.52916667 -0.525 -0.52083333 -0.51666667 -0.5125 -0.50833333 -0.50416667 -0.5 -0.49583333 -0.49166667 -0.4875 -0.48333333 -0.47916667 -0.475 -0.47083333 -0.46666667 -0.4625 -0.45833333 -0.45416667 -0.45 -0.44583333 -0.44166667 -0.4375 -0.43333333 -0.42916667 -0.425 -0.42083333 -0.41666667 -0.4125 -0.40833333 -0.40416667 -0.4 -0.39583333 -0.39166667 -0.3875 -0.38333333 -0.37916667 -0.375 -0.37083333 -0.36666667 -0.3625 -0.35833333 -0.35416667 -0.35 -0.34583333 -0.34166667 -0.3375 -0.33333333 -0.32916667 -0.325 -0.32083333 -0.31666667 -0.3125 -0.30833333 -0.30416667 -0.3 -0.29583333 -0.29166667 -0.2875 -0.28333333 -0.27916667 -0.275 -0.27083333 -0.26666667 -0.2625 -0.25833333 -0.25416667 -0.25 -0.24583333 -0.24166667 -0.2375 -0.23333333 -0.22916667 -0.225 -0.22083333 -0.21666667 -0.2125 -0.20833333 -0.20416667 -0.2 -0.19583333 -0.19166667 -0.1875 -0.18333333 -0.17916667 -0.175 -0.17083333 -0.16666667 -0.1625 -0.15833333 -0.15416667 -0.15 -0.14583333 -0.14166667 -0.1375 -0.13333333 -0.12916667 -0.125 -0.12083333 -0.11666667 -0.1125 -0.10833333 -0.10416667 -0.1 -0.09583333 -0.09166667 -0.0875 -0.08333333 -0.07916667 -0.075 -0.07083333 -0.06666667 -0.0625 -0.05833333 -0.05416667 -0.05 -0.04583333 -0.04166667 -0.0375 -0.03333333 -0.02916667 -0.025 -0.02083333 -0.01666667 -0.0125 -0.00833333 -0.00416667 0 0 0 0 0 0
  line L38 (-0.790203, 5.75544) -> (-0.790134, 5.754897)
  line L39 (-0.790134, 5.754897) -> (-0.646102, 4.705853)
  arc A20 (-0.646102, 4.705853) -> (-1.793385, 4.398439) centre (0, 0) ccw
  line L40 (-1.793385, 4.398439) -> (-2.193173, 5.378954)
  line L41 (-2.193173, 5.378954) -> (-2.193384, 5.379459)
  spline S20 degree 5 poles (-2.193384, 5.379459) (-2.193405, 5.379509) (-2.19345, 5.379616) (-2.193526, 5.379794) (-2.193643, 5.380067) (-2.193817, 5.380467) (-2.194018, 5.380926) (-2.194247, 5.381443) (-2.194504, 5.382019) (-2.194788, 5.382652) (-2.195101, 5.383341) (-2.195442, 5.384086) (-2.195811, 5.384885) (-2.196209, 5.385739) (-2.196636, 5.386647) (-2.197091, 5.387608) (-2.197576, 5.388622) (-2.19809, 5.389688) (-2.198633, 5.390805) (-2.199206, 5.391973) (-2.199808, 5.393192) (-2.20044, 5.39446) (-2.201102, 5.395777) (-2.201794, 5.397143) (-2.202515, 5.398557) (-2.203268, 5.400019) (-2.20405, 5.401528) (-2.204863, 5.403083) (-2.205707, 5.404684) (-2.206581, 5.406331) (-2.207486, 5.408023) (-2.208422, 5.40976) (-2.209389, 5.41154) (-2.210387, 5.413364) (-2.211416, 5.415231) (-2.212477, 5.417141) (-2.213569, 5.419092) (-2.214692, 5.421086) (-2.215847, 5.42312) (-2.217034, 5.425195) (-2.218252, 5.427311) (-2.219503, 5.429466) (-2.220785, 5.431661) (-2.2221, 5.433895) (-2.223446, 5.436167) (-2.224825, 5.438478) (-2.226236, 5.440826) (-2.227679, 5.443211) (-2.229155, 5.445633) (-2.230663, 5.448092) (-2.232203, 5.450586) (-2.233777, 5.453116) (-2.235383, 5.455682) (-2.237022, 5.458282) (-2.238693, 5.460917) (-2.240398, 5.463585) (-2.242135, 5.466288) (-2.243906, 5.469023) (-2.245709, 5.471792) (-2.247546, 5.474593) (-2.249416, 5.477426) (-2.251319, 5.480291) (-2.253255, 5.483187) (-2.255225, 5.486114) (-2.257228, 5.489072) (-2.259264, 5.492061) (-2.261334, 5.495079) (-2.263438, 5.498127) (-2.265575, 5.501204) (-2.267746, 5.50431) (-2.26995, 5.507445) (-2.272188, 5.510608) (-2.27446, 5.513799) (-2.276766, 5.517018) (-2.279105, 5.520264) (-2.281478, 5.523536) (-2.283885, 5.526836) (-2.286326, 5.530161) (-2.288801, 5.533513) (-2.29131, 5.53689) (-2.293854, 5.540293) (-2.296431, 5.54372) (-2.299042, 5.547172) (-2.301687, 5.550649) (-2.304367, 5.55415) (-2.30708, 5.557674) (-2.309828, 5.561222) (-2.31261, 5.564793) (-2.315426, 5.568387) (-2.318277, 5.572004) (-2.321161, 5.575643) (-2.32408, 5.579304) (-2.327034, 5.582987) (-2.330022, 5.586691) (-2.333044, 5.590416) (-2.3361, 5.594162) (-2.339191, 5.597929) (-2.342316, 5.601716) (-2.345476, 5.605523) (-2.34867, 5.609349) (-2.351898, 5.613196) (-2.355161, 5.617061) (-2.358459, 5.620945) (-2.361791, 5.624848) (-2.365157, 5.62877) (-2.368558, 5.632709) (-2.371994, 5.636667) (-2.375463, 5.640642) (-2.378968, 5.644634) (-2.382507, 5.648644) (-2.38608, 5.65267) (-2.389688, 5.656713) (-2.393331, 5.660772) (-2.397008, 5.664848) (-2.40072, 5.668939) (-2.404466, 5.673046) (-2.408247, 5.677168) (-2.412062, 5.681305) (-2.415912, 5.685457) (-2.419796, 5.689624) (-2.423715, 5.693805) (-2.427668, 5.698) (-2.431656, 5.702209) (-2.435679, 5.706432) (-2.439736, 5.710668) (-2.443827, 5.714918) (-2.447953, 5.71918) (-2.452114, 5.723455) (-2.456309, 5.727743) (-2.460538, 5.732042) (-2.464802, 5.736354) (-2.469101, 5.740678) (-2.473433, 5.745013) (-2.477801, 5.74936) (-2.482203, 5.753718) (-2.486639, 5.758087) (-2.49111, 5.762466) (-2.495615, 5.766856) (-2.500154, 5.771256) (-2.504728, 5.775667) (-2.509336, 5.780087) (-2.513979, 5.784517) (-2.518656, 5.788956) (-2.523367, 5.793404) (-2.528112, 5.797862) (-2.532892, 5.802328) (-2.537706, 5.806803) (-2.542554, 5.811286) (-2.547437, 5.815778) (-2.552354, 5.820277) (-2.557305, 5.824785) (-2.56229, 5.829299) (-2.567309, 5.833822) (-2.572363, 5.838351) (-2.57745, 5.842887) (-2.582572, 5.84743) (-2.587728, 5.85198) (-2.592917, 5.856536) (-2.598141, 5.861098) (-2.603399, 5.865667) (-2.608691, 5.870241) (-2.614016, 5.874821) (-2.619376, 5.879406) (-2.62477, 5.883996) (-2.630197, 5.888592) (-2.635658, 5.893192) (-2.641154, 5.897797) (-2.646683, 5.902407) (-2.652245, 5.90702) (-2.657842, 5.911638) (-2.663472, 5.91626) (-2.669136, 5.920886) (-2.674833, 5.925515) (-2.680564, 5.930148) (-2.686329, 5.934784) (-2.692128, 5.939423) (-2.697959, 5.944064) (-2.703825, 5.948709) (-2.709724, 5.953356) (-2.715656, 5.958005) (-2.721622, 5.962657) (-2.727621, 5.96731) (-2.733653, 5.971966) (-2.739719, 5.976622) (-2.745818, 5.981281) (-2.75195, 5.985941) (-2.758116, 5.990602) (-2.764315, 5.995264) (-2.770546, 5.999926) (-2.776811, 6.00459) (-2.78311, 6.009253) (-2.789441, 6.013918) (-2.795805, 6.018582) (-2.802202, 6.023246) (-2.808632, 6.02791) (-2.815095, 6.032574) (-2.82159, 6.037237) (-2.828119, 6.0419) (-2.83468, 6.046562) (-2.841274, 6.051223) (-2.847901, 6.055882) (-2.854561, 6.060541) (-2.861253, 6.065198) (-2.867977, 6.069853) (-2.874735, 6.074507) (-2.881524, 6.079158) (-2.888347, 6.083808) (-2.895201, 6.088455) (-2.902088, 6.0931) (-2.909007, 6.097743) (-2.915959, 6.102382) (-2.922943, 6.107019) (-2.929959, 6.111653) (-2.937007, 6.116284) (-2.944088, 6.120912) (-2.9512, 6.125536) (-2.958345, 6.130157) (-2.965521, 6.134774) (-2.97273, 6.139387) (-2.97997, 6.143996) (-2.987242, 6.148601) (-2.994546, 6.153201) (-3.001882, 6.157797) (-3.00925, 6.162389) (-3.016649, 6.166976) (-3.02408, 6.171558) (-3.031542, 6.176135) (-3.039036, 6.180707) (-3.046562, 6.185273) (-3.054119, 6.189834) (-3.061707, 6.19439) (-3.069327, 6.19894) (-3.076978, 6.203484) (-3.084661, 6.208022) (-3.092374, 6.212555) (-3.100119, 6.21708) (-3.107895, 6.2216) (-3.115701, 6.226112) (-3.123539, 6.230618) (-3.131408, 6.235117) (-3.139308, 6.23961) (-3.145652, 6.243199) (-3.150425, 6.245887) (-3.153612, 6.247678) (-3.155208, 6.248573) knots 0 0 0 0 0 0 0.00416667 0.00833333 0.0125 0.01666667 0.02083333 0.025 0.02916667 0.03333333 0.0375 0.04166667 0.04583333 0.05 0.05416667 0.05833333 0.0625 0.06666667 0.07083333 0.075 0.07916667 0.08333333 0.0875 0.09166667 0.09583333 0.1 0.10416667 0.10833333 0.1125 0.11666667 0.12083333 0.125 0.12916667 0.13333333 0.1375 0.14166667 0.14583333 0.15 0.15416667 0.15833333 0.1625 0.16666667 0.17083333 0.175 0.17916667 0.18333333 0.1875 0.19166667 0.19583333 0.2 0.20416667 0.20833333 0.2125 0.21666667 0.22083333 0.225 0.22916667 0.23333333 0.2375 0.24166667 0.24583333 0.25 0.25416667 0.25833333 0.2625 0.26666667 0.27083333 0.275 0.27916667 0.28333333 0.2875 0.29166667 0.29583333 0.3 0.30416667 0.30833333 0.3125 0.31666667 0.32083333 0.325 0.32916667 0.33333333 0.3375 0.34166667 0.34583333 0.35 0.35416667 0.35833333 0.3625 0.36666667 0.37083333 0.375 0.37916667 0.38333333 0.3875 0.39166667 0.39583333 0.4 0.40416667 0.40833333 0.4125 0.41666667 0.42083333 0.425 0.42916667 0.43333333 0.4375 0.44166667 0.44583333 0.45 0.45416667 0.45833333 0.4625 0.46666667 0.47083333 0.475 0.47916667 0.48333333 0.4875 0.49166667 0.49583333 0.5 0.50416667 0.50833333 0.5125 0.51666667 0.52083333 0.525 0.52916667 0.53333333 0.5375 0.54166667 0.54583333 0.55 0.55416667 0.55833333 0.5625 0.56666667 0.57083333 0.575 0.57916667 0.58333333 0.5875 0.59166667 0.59583333 0.6 0.60416667 0.60833333 0.6125 0.61666667 0.62083333 0.625 0.62916667 0.63333333 0.6375 0.64166667 0.64583333 0.65 0.65416667 0.65833333 0.6625 0.66666667 0.67083333 0.675 0.67916667 0.68333333 0.6875 0.69166667 0.69583333 0.7 0.70416667 0.70833333 0.7125 0.71666667 0.72083333 0.725 0.72916667 0.73333333 0.7375 0.74166667 0.74583333 0.75 0.75416667 0.75833333 0.7625 0.76666667 0.77083333 0.775 0.77916667 0.78333333 0.7875 0.79166667 0.79583333 0.8 0.80416667 0.80833333 0.8125 0.81666667 0.82083333 0.825 0.82916667 0.83333333 0.8375 0.84166667 0.84583333 0.85 0.85416667 0.85833333 0.8625 0.86666667 0.87083333 0.875 0.87916667 0.88333333 0.8875 0.89166667 0.89583333 0.9 0.90416667 0.90833333 0.9125 0.91666667 0.92083333 0.925 0.92916667 0.93333333 0.9375 0.94166667 0.94583333 0.95 0.95416667 0.95833333 0.9625 0.96666667 0.97083333 0.975 0.97916667 0.98333333 0.9875 0.99166667 0.99583333 1 1 1 1 1 1
  arc A21 (-3.155208, 6.248573) -> (-3.833819, 5.856777) centre (0, 0) ccw